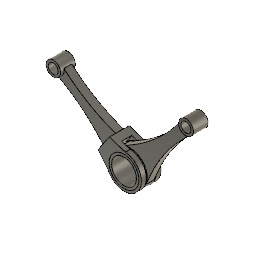
own conbined BFGG (Autodesk Fusion 360 design; units mm, degrees)
Autodesk Fusion 360 part; units mm, degrees
sketch "Sketch1" plane through (0, 0, 0) normal (0, 1, 0) x (1, 0, 0) in component "onw fork v0"
  circle A0 centre (0, 0) radius 30
  circle A1 centre (0, -180) radius 10
  circle A2 centre (0, -180) radius 15
  spline S0 degree 5 poles (-11.5318, -170.4075) (-11.217, -167.5211) (-10.6485, -161.7338) (-9.9789, -153.0088) (-9.4585, -141.286) (-9.4697, -126.4735) (-10.1979, -111.4888) (-11.6955, -96.3192) (-13.9797, -80.9606) (-17.0074, -65.4233) (-20.7173, -49.7222) (-24.1837, -37.0415) (-27.0457, -27.468) (-29.0683, -21.0581) (-30.1083, -17.8463) knots 0 0 0 0 0 0 0.1 0.2 0.3 0.4 0.5 0.6 0.7 0.8 0.9 1 1 1 1 1 1
  spline S1 degree 5 poles (11.5318, -170.4075) (11.217, -167.5211) (10.6485, -161.7338) (9.9789, -153.0088) (9.4585, -141.286) (9.4697, -126.4735) (10.1979, -111.4888) (11.6955, -96.3192) (13.9797, -80.9606) (17.0074, -65.4233) (20.7173, -49.7222) (24.1837, -37.0415) (27.0457, -27.468) (29.0683, -21.0581) (30.1083, -17.8463) knots 0 0 0 0 0 0 0.1 0.2 0.3 0.4 0.5 0.6 0.7 0.8 0.9 1 1 1 1 1 1
  line L0 (-13.2185, -185.8726) -> (-9.8451, -154.9423)
  line L1 (-24.9683, -33.7207) -> (-35.2483, -1.9719)
  line L2 (13.2185, -185.8726) -> (9.8451, -154.9423)
  line L3 (24.9683, -33.7207) -> (35.2483, -1.9719)
  line L4 (0, -165) -> (0, -180)
  line L5 (-20.7903, -50.011) -> (20.7903, -50.011)
  arc A3 (30.1083, -17.8463) -> (-30.1083, -17.8463) centre (0, 0) ccw
  point P0 (-11.5318, -99.2981)
  point P1 (11.5318, -99.2981)
  point P2 (11.5318, -99.2981)
  dimension "d1" = 180
  dimension "d2" = 70
  dimension "d3" = 60
  dimension "d4" = 20
  dimension "d5" = 30
  constraint coincident A0.centre A3.centre
  constraint concentric A0 A3
  constraint coincident A1.centre A2.centre
  constraint concentric A1 A2
  constraint coincident A2 S0.start
  constraint midpoint S0.start L0
  constraint midpoint S0.end L1
  constraint coincident A2 L4.start
  constraint coincident S0 L5.start
  constraint coincident S1 L5.end
  constraint horizontal L5
  measures "d1" distance of A0.centre A1.centre
  measures "d2" diameter of A3
  measures "d3" diameter of A0
  measures "d4" diameter of A1
  measures "d5" diameter of A2
extrude "Extrude1" add sketch "Sketch1" along normal mid plane 40 contours S0 S1 L1 L3 L5 A3 | L3 A3 | L1 A3 makes body 1 in component "onw fork v0"
extrude "Extrude2" add sketch "Sketch1" along normal mid plane 16 contours A2 S0 S1 L5 bodies 1 in component "onw fork v0"
extrude "Extrude3" add sketch "Sketch1" along normal mid plane 30 contours A2 bodies 1 in component "onw fork v0"
sketch "Sketch2" plane through (0, 0, 0) normal (1, 0, 0) x (0, 1, 0) in component "onw fork v0"
  line L0 (10, -35) -> (-10, -35)
  line L1 (-10, -35) -> (-10, 35)
  line L2 (-10, 35) -> (10, 35)
  line L3 (10, 35) -> (10, -35)
  line L4 (10, -35) -> (-10, 35) construction
  line L5 (-10, -35) -> (10, 35) construction
  dimension "d12" = 20
  dimension "d13" = 70
  constraint horizontal L0
  constraint perpendicular L0 L1
  constraint parallel L0 L2
  constraint parallel L1 L3
  constraint coincident L4 origin
  constraint coincident L5 origin
  measures "d12" distance of L1.end L2.end
  measures "d13" distance of L0.end L1.end
extrude "Extrude4" cut sketch "Sketch2" along normal mid plane 100 bodies 1 in component "onw fork v0"
sketch "Sketch1 (2)" plane through (0, 0, 0) normal (0, 1, 0) x (1, 0, 0) in component "onw cont rod v0"
  circle A0 centre (0, 0) radius 35
  circle A1 centre (0, 0) radius 30
  circle A2 centre (0, 0) radius 25
  circle A3 centre (0, -180) radius 15
  circle A4 centre (0, -180) radius 10
  spline S0 degree 5 poles (-12.8019, -172.1827) (-12.4433, -168.8616) (-11.7919, -162.2309) (-11.0124, -152.3184) (-10.3744, -139.1705) (-10.2918, -122.8578) (-10.9883, -106.6784) (-12.5285, -90.6431) (-14.9491, -74.7584) (-18.2173, -59.0186) (-22.27, -43.4129) (-26.0887, -31.0269) (-29.2564, -21.7894) (-31.5011, -15.6537) (-32.6566, -12.5916) knots 0 0 0 0 0 0 0.1 0.2 0.3 0.4 0.5 0.6 0.7 0.8 0.9 1 1 1 1 1 1
  spline S1 degree 5 poles (12.8019, -172.1827) (12.4433, -168.8616) (11.7919, -162.2309) (11.0124, -152.3184) (10.3744, -139.1705) (10.2918, -122.8578) (10.9883, -106.6784) (12.5285, -90.6431) (14.9491, -74.7584) (18.2173, -59.0186) (22.27, -43.4129) (26.0887, -31.0269) (29.2564, -21.7894) (31.5011, -15.6537) (32.6566, -12.5916) knots 0 0 0 0 0 0 0.1 0.2 0.3 0.4 0.5 0.6 0.7 0.8 0.9 1 1 1 1 1 1
  line L0 (-14.6323, -189.1343) -> (-10.9715, -155.231)
  line L1 (-26.6934, -28.3942) -> (-38.6197, 3.211)
  line L2 (14.6323, -189.1343) -> (10.9715, -155.231)
  line L3 (26.6934, -28.3942) -> (38.6197, 3.211)
  point P0 (-12.8019, -90.2486)
  point P1 (12.8019, -90.2486)
  dimension "d1_1" = 180
  dimension "d2_1" = 70
  dimension "d3_1" = 60
  dimension "d4_1" = 50
  dimension "d5_1" = 30
  dimension "d6_1" = 20
  constraint coincident A0.centre A1.centre
  constraint concentric A0 A2
  constraint concentric A3 A4
  constraint coincident A3 S0.start
  constraint coincident A0 S0.end
  constraint midpoint S0.start L0
  constraint midpoint S0.end L1
  measures "d1_1" distance of A0.centre A3.centre
  measures "d2_1" diameter of A0
  measures "d3_1" diameter of A1
  measures "d4_1" diameter of A2
  measures "d5_1" diameter of A3
  measures "d6_1" diameter of A4
extrude "Extrude1'" add sketch "Sketch1 (2)" along normal mid plane 16 separate body contours A0 A3 S0 S1 makes body 2 in component "onw cont rod v0"
extrude "Extrude2'" add sketch "Sketch1 (2)" along normal mid plane 20 contours A0 bodies 2 in component "onw cont rod v0"
extrude "Extrude3'" add sketch "Sketch1 (2)" along normal mid plane 40 contours A1 bodies 2 in component "onw cont rod v0"
extrude "Extrude4'" add sketch "Sketch1 (2)" along normal mid plane 30 contours A3 L0 | A3 L0 L2 | A3 L2 bodies 2 in component "onw cont rod v0"
component "onw fork v0" placed x (1, 0, 0) y (0, 1, 0) z (0, 0, 1) at (0, 0, 0)
component "onw cont rod v0" placed x (1, 0, 0) y (0, 1, 0) z (0, 0, 1) at (0, 0, 0)
